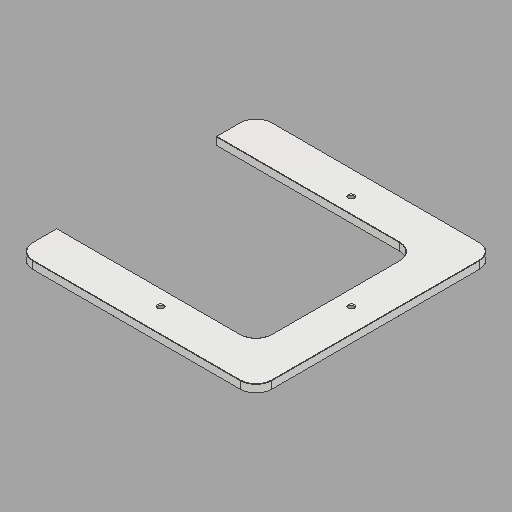
# Autodesk Inventor part: BT026_thutrn22_26
Saved by Autodesk Inventor 2025.3 (Build 293356000, 356)
## iProperties
Company: HTBLA Kaindorf
RuleStatus: InUse
Created: 2026-08-19
Part Number: BT026_thutrn22_26
Project: Biegeroboter
Material: ABS-Kunststoff
Description: gehaeuse_getriebe_deckel_oben
Document SubType Name: Modeling
Designer: thutrn22
Density: 1.06 g/cm^3
Appearance: Glatt - Weiß
Mass: 52.6038 g
Surface Area: 239.392 cm^2
Volume: 49.6263 cm^3
AfterDocNew0: iProperties-Editor_aufrufen
Author: trist
Keywords: 2026
Autodesk Inventor part; units mm, degrees
ref_plane "YZ Plane" through (0, 0, 0) normal (1, 0, 0) x (0, 1, 0)
ref_plane "XZ Plane" through (0, 0, 0) normal (0, 1, 0) x (-1, 0, 0)
ref_plane "XY Plane" through (0, 0, 0) normal (0, 0, 1) x (1, 0, 0)
sketch "Skizze3" plane through (0, 0, 0) normal (0, 0, 1) x (1, 0, 0)
  line L0 (-105, 0) -> (105, 0) projected
  line L1 (0, -111) -> (0, 106) projected
  line L2 (-75, 75) -> (75, 75)
  line L3 (75, 75) -> (75, -75)
  line L4 (75, -75) -> (-75, -75)
  line L5 (-75, -75) -> (-75, 75)
  line L6 (-50, 50) -> (50, 50)
  line L7 (50, 50) -> (50, -50)
  line L8 (50, -50) -> (-50, -50)
  line L9 (-50, -50) -> (-50, 50)
  line L10 (-50, 20) -> (-69.5, 20)
  line L11 (-69.5, 20) -> (-69.5, -20)
  line L12 (-69.5, -20) -> (-50, -20)
  line L13 (50, 20) -> (69.5, 20)
  line L14 (69.5, 20) -> (69.5, -20)
  line L15 (69.5, -20) -> (50, -20)
  line L16 (-19.3205, 50) -> (0.1795, 50) construction
  line L17 (-20, 50) -> (-20, 69.5)
  line L18 (-20, 69.5) -> (20, 69.5)
  line L19 (20, 69.5) -> (20, 50)
  line L20 (-50, -50) -> (50, -50)
  line L21 (50, -50) -> (50, -80)
  line L22 (50, -80) -> (-50, -80)
  line L23 (-50, -80) -> (-50, -50)
  point P0 (0, 0)
  dimension "d4" = 150
  dimension "d5" = 150
  dimension "d6" = 100
  dimension "d7" = 100
  dimension "d11" = 19.5
  dimension "d12" = 40
  dimension "d13" = 55
  dimension "d14" = 19.5
  dimension "d15" = 40
  dimension "d16" = 55
  dimension "d19" = 19.5
  dimension "d20" = 40
  dimension "d21" = 55
  dimension "d58" = 30
  constraints: 44 end point, 10 perpendicular, 7 parallel, 7 point on line, 4 horizontal, 4 other
  measures "d4" distance of L3.end L4.end
  measures "d5" distance of L2.end L3.end
  measures "d6" distance of L7.end L8.end
  measures "d7" distance of L6.end L7.end
  measures "d11" distance of L10.start L10.end
  measures "d12" distance of L10.end L11.end
  measures "d13" distance between parallel lines of L2 L10
  measures "d14" distance of L13.start L13.end
  measures "d15" distance of L13.end L14.end
  measures "d16" distance between parallel lines of L2 L13
  measures "d19" distance of L17.start L17.end
  measures "d20" distance of L17.end L18.end
  measures "d21" distance between parallel lines of L5 L17
  measures "d58" distance of L20.end L21.end
extrude "Extrusion8" add sketch "Skizze3" along normal blind 5 contours L5 L2 L1 L18 L17 L6 L9 L10 L11 L0 | L0 L11 L12 L9 L23 L4 L5 | L11 L10 L9 L0 | L0 L9 L12 L11 | L2 L3 L0 L14 L13 L7 L6 L19 L18 L1 | L18 L19 L6 L1 | L1 L6 L17 L18 | L7 L13 L14 L0 | L0 L14 L15 L7 | L21 L7 L15 L14 L0 L3 L4
fillet "Rundung3" radius 10 6 edges at (75, 75, 2.5) (-75, 75, 2.5) (75, -75, 2.5) (-75, -75, 2.5) (50, 50, 2.5) (-50, 50, 2.5)
sketch "Skizze8" plane through (0, 0, 5) normal (0, 0, 1) x (1, 0, 0)
  line L0 (65, 75) -> (-65, 75) projected
  line L1 (50, -75) -> (65, -75) projected
  line L2 (-65, -75) -> (-50, -75) projected
  line L3 (75, -65) -> (75, 65) projected
  line L4 (-75, 65) -> (-75, -65) projected
  point P0 (0, 0)
  point P1 (59.75, 0)
  point P2 (0, 59.75)
  point P3 (-59.75, 0)
  point P4 (0, 75)
  dimension "d62" = 75
  dimension "d63" = 75
  dimension "d64" = 75
  dimension "d65" = 15.25
  dimension "d66" = 15.25
  dimension "d67" = 15.25
  constraints: 1 midpoint
  measures "d62" distance from line of L1 point (59.75, 0)
  measures "d63" distance from line of L3 point (0, 59.75)
  measures "d64" distance from line of L2 point (-59.75, 0)
  measures "d65" distance from line of L4 point (-59.75, 0)
  measures "d66" distance of point (0, 75) point (0, 59.75)
  measures "d67" distance from line of L3 point (59.75, 0)
hole "Bohrung1" at (59.75, 0, 5) at (0, 59.75, 5) at (-59.75, 0, 5) direction (0, 0, -1) diameter 3.242 depth 11.8 tip angle 118 countersink diameter 4 countersink angle 90 thread size "M4x0.7" class "6H" standard "ISO Metric profile"
chamfer "Fasen4" distance 0.2 angle 45 24 edges at (-50, -17.5, 5) (0, 50, 5) (50, -17.5, 5) (0, 75, 5) (-72.0711, 72.0711, 5) (-75, 0, 5) (-72.0711, -72.0711, 5) (-57.5, -75, 5) (72.0711, 72.0711, 5) (75, 0, 5) (72.0711, -72.0711, 5) (57.5, -75, 5) (0, 75, 0) (-72.0711, 72.0711, 0) (-75, 0, 0) (-72.0711, -72.0711, 0) (-57.5, -75, 0) (72.0711, 72.0711, 0) (75, 0, 0) (72.0711, -72.0711, 0) (57.5, -75, 0) (50, -17.5, 0) (0, 50, 0) (-50, -17.5, 0)
